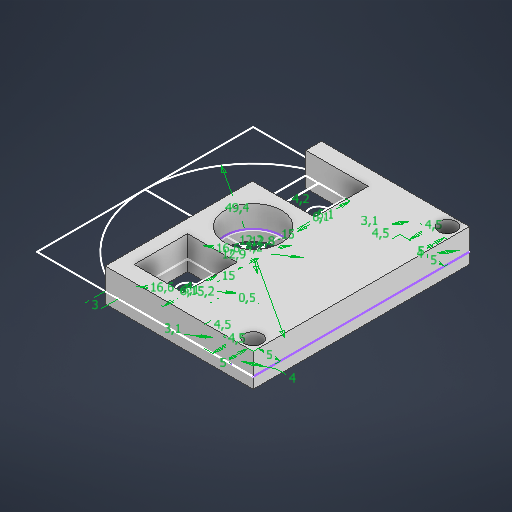
# Autodesk Inventor part: peça1
Saved by Autodesk Inventor 2026.2 (Build 302298010, 298A)
## iProperties
Created: 2026-04-17
Part Number: peça1
Material: Genérico
Document SubType Name: Modeling
Designer: a2453266
Density: 1 g/cm^3
Appearance: Padrão
Author: a2453266
## iProperties of the stored document peça1_3DPrint.ipt
Created: 2026-04-17
Part Number: peça1_3DPrint
Material: Genérico
Document SubType Name: Modeling
Designer: a2453266
Density: 1 g/cm^3
Appearance: Padrão
Author: a2453266
Autodesk Inventor part; units mm, degrees
ref_plane "YZ Plane" through (0, 0, 0) normal (1, 0, 0) x (0, 1, 0)
ref_plane "XZ Plane" through (0, 0, 0) normal (0, 1, 0) x (-1, 0, 0)
ref_plane "XY Plane" through (0, 0, 0) normal (0, 0, 1) x (1, 0, 0)
sketch "Esboço1" plane through (0, 0, 0) normal (0, 1, 0) x (-1, 0, 0)
  circle A0 centre (0, 0) radius 2.1
  line L0 (0, 0) -> (0, 15)
  circle A1 centre (0, 15) radius 2
  line L1 (0, 0) -> (0, -15)
  circle A2 centre (0, -15) radius 2.1
  line L2 (0, 15) -> (-5.2, 15)
  line L3 (-5.2, 15) -> (-5.2, -15)
  line L4 (-5.2, -15) -> (0, -15)
  circle A3 centre (0, 0) radius 6.1
  circle A4 centre (0, 0) radius 24.7
  line L5 (0, 24.7) -> (24.7, 24.7)
  line L6 (24.7, 24.7) -> (24.7, 0)
  line L7 (24.7, 0) -> (0, 0)
  line L8 (0, 0) -> (0, 24.7)
  line L9 (24.7, 0) -> (0, 0)
  line L10 (0, 0) -> (0, -24.7)
  line L11 (0, -24.7) -> (24.7, -24.7)
  line L12 (24.7, -24.7) -> (24.7, 0)
  line L13 (0, -24.7) -> (-24.7, -24.7)
  line L14 (-24.7, -24.7) -> (-24.7, 0)
  line L15 (-24.7, 0) -> (0, 0)
  line L16 (0, 0) -> (0, -24.7)
  line L17 (0, 24.7) -> (-24.7, 24.7)
  line L18 (-24.7, 24.7) -> (-24.7, 0)
  line L19 (-24.7, 0) -> (0, 0)
  line L20 (0, 0) -> (0, 24.7)
  line L21 (-5.2, 15) -> (-5.2, 24.7)
  line L22 (-5.2, -15) -> (-5.2, -24.7)
  line L23 (-5.2, 24.7) -> (-24.7, 24.7)
  line L24 (-24.7, 24.7) -> (-24.7, -24.7)
  line L25 (-24.7, -24.7) -> (-5.2, -24.7)
  line L26 (-5.2, -24.7) -> (-5.2, 24.7)
  line L27 (0, -15) -> (0, -21.1)
  line L28 (0, -21.1) -> (-5.2, -21.1)
  line L29 (0, -15) -> (0, -8.9)
  line L30 (0, -8.9) -> (-5.2, -8.9)
  line L31 (0, -8.9) -> (0, -15)
  line L32 (0, 15) -> (0, 8.9)
  line L33 (0, 15) -> (0, 21.1)
  line L34 (0, 21.1) -> (-5.2, 21.1)
  line L35 (0, 8.9) -> (-5.2, 8.9)
  line L36 (6.1, 0) -> (6.1, -24.7)
  line L37 (6.1, 0) -> (6.1, 24.7)
  line L38 (-5.2, 21.1) -> (6.1, 21.1)
  line L39 (6.1, 21.1) -> (6.1, 24.7)
  line L40 (6.1, 24.7) -> (-5.2, 24.7)
  line L41 (-5.2, 24.7) -> (-5.2, 21.1)
  line L42 (-5.2, -21.1) -> (6.1, -21.1)
  line L43 (6.1, -21.1) -> (6.1, -24.7)
  line L44 (6.1, -24.7) -> (-5.2, -24.7)
  line L45 (-5.2, -24.7) -> (-5.2, -21.1)
  line L46 (6.1, 21.1) -> (0, 21.1)
  line L47 (0, 21.1) -> (0, 8.9)
  line L48 (0, 8.9) -> (6.1, 8.9)
  line L49 (6.1, 8.9) -> (6.1, 21.1)
  line L50 (0, -8.9) -> (6.1, -8.9)
  line L51 (6.1, -8.9) -> (6.1, -21.1)
  line L52 (6.1, -21.1) -> (0, -21.1)
  line L53 (0, -21.1) -> (0, -8.9)
  line L54 (6.1, -24.7) -> (9.1, -24.7)
  line L55 (9.1, -24.7) -> (9.1, 24.7)
  line L56 (9.1, 24.7) -> (6.1, 24.7)
  line L57 (6.1, 24.7) -> (6.1, -24.7)
  circle A5 centre (0, 0) radius 8.3
  circle A6 centre (0, 15) radius 8.3
  line L58 (-5.2, -8.9) -> (-24.7, -8.9)
  line L59 (-24.7, -8.9) -> (-24.7, -24.7)
  line L60 (-24.7, -24.7) -> (-5.2, -24.7)
  line L61 (-5.2, -24.7) -> (-5.2, -8.9)
  line L62 (-5.2, 8.9) -> (-24.7, 8.9)
  line L63 (-24.7, 8.9) -> (-24.7, 24.7)
  line L64 (-24.7, 24.7) -> (-5.2, 24.7)
  line L65 (-5.2, 24.7) -> (-5.2, 8.9)
  line L66 (-8.3, 0) -> (-8.3, -8.9)
  line L67 (-8.3, 0) -> (-8.3, 8.9)
  line L68 (-8.3, -8.9) -> (-8.8, -8.9)
  line L69 (-8.8, -8.9) -> (-8.8, 8.9)
  line L70 (-8.8, 8.9) -> (-8.3, 8.9)
  line L71 (-8.3, 8.9) -> (-8.3, -8.9)
  line L72 (-8.8, -8.9) -> (-24.7, -8.9)
  line L73 (-24.7, -8.9) -> (-24.7, -24.7)
  line L74 (-24.7, -24.7) -> (-8.8, -24.7)
  line L75 (-8.8, -24.7) -> (-8.8, -8.9)
  line L76 (-8.8, -8.9) -> (-24.7, -8.9)
  line L77 (-24.7, -8.9) -> (-24.7, 24.7)
  line L78 (-24.7, 24.7) -> (-8.8, 24.7)
  line L79 (-8.8, 24.7) -> (-8.8, -8.9)
  line L80 (9.1, -24.7) -> (6.1, -24.7)
  line L81 (6.1, -24.7) -> (6.1, -21.1)
  line L82 (6.1, -21.1) -> (9.1, -21.1)
  line L83 (9.1, -21.1) -> (9.1, -24.7)
  line L84 (6.1, 21.1) -> (9.1, 21.1)
  line L85 (9.1, 21.1) -> (9.1, 24.7)
  line L86 (9.1, 24.7) -> (6.1, 24.7)
  line L87 (6.1, 24.7) -> (6.1, 21.1)
  line L88 (9.1, 24.7) -> (9.1, 22.9)
  line L89 (-24.7, -24.7) -> (-21.7, -24.7)
  line L90 (-24.7, -21.1) -> (-24.7, -24.7)
  line L91 (-24.7, 24.7) -> (-21.7, 24.7)
  line L92 (-24.7, 21.1) -> (-24.7, 24.7)
  line L93 (-24.7, -24.7) -> (-20.2, -24.7)
  line L94 (-24.7, -20.2) -> (-24.7, -24.7)
  line L95 (-24.7, 24.7) -> (-20.2, 24.7)
  line L96 (-24.7, 20.2) -> (-24.7, 24.7)
  line L97 (-8.8, -24.7) -> (-13.3, -24.7)
  line L98 (-13.3, -24.7) -> (-13.3, -20.2)
  line L99 (-13.3, -20.2) -> (-8.8, -20.2)
  line L100 (-8.8, -20.2) -> (-8.8, -24.7)
  line L101 (-8.8, 24.7) -> (-13.3, 24.7)
  line L102 (-13.3, 24.7) -> (-13.3, 20.2)
  line L103 (-13.3, 20.2) -> (-8.8, 20.2)
  line L104 (-8.8, 20.2) -> (-8.8, 24.7)
  line L105 (-13.3, -22.45) -> (-8.8, -22.45)
  line L106 (-8.8, 22.45) -> (-13.3, 22.45)
  circle A7 centre (-11.05, -22.45) radius 1.55
  circle A8 centre (-11.05, 22.45) radius 1.55
  circle A9 centre (0, 0) radius 6.4
  line L107 (9.1, 21.1) -> (6.1, 21.1)
  line L108 (6.1, 21.1) -> (6.1, 8.9)
  line L109 (6.1, 8.9) -> (9.1, 8.9)
  line L110 (9.1, 8.9) -> (9.1, 21.1)
  line L111 (6.1, -8.9) -> (9.1, -8.9)
  line L112 (9.1, -8.9) -> (9.1, -21.1)
  line L113 (9.1, -21.1) -> (6.1, -21.1)
  line L114 (6.1, -21.1) -> (6.1, -8.9)
  line L115 (-24.7, -24.7) -> (-19.7, -24.7)
  line L116 (-19.7, -24.7) -> (-19.7, -19.7)
  line L117 (-19.7, -19.7) -> (-24.7, -19.7)
  line L118 (-24.7, -19.7) -> (-24.7, -24.7)
  line L119 (-19.7, -22.2) -> (-24.7, -22.2)
  line L120 (-24.7, 24.7) -> (-19.7, 24.7)
  line L121 (-19.7, 24.7) -> (-19.7, 19.7)
  line L122 (-19.7, 19.7) -> (-24.7, 19.7)
  line L123 (-24.7, 19.7) -> (-24.7, 24.7)
  line L124 (-19.7, 22.2) -> (-24.7, 22.2)
  circle A10 centre (-22.2, -22.2) radius 2
  circle A11 centre (-22.2, 22.2) radius 2
  circle A12 centre (0, 0) radius 6.45
  point P0 (-5.2, -3.189)
  point P1 (-5.2, 3.189)
  point P2 (-5.2, 24.1464)
  point P3 (-5.2, -24.1464)
  point P4 (6.1, -21.1)
  point P5 (6.1, 21.1)
  point P6 (6.1, -21.1)
  point P7 (-5.2, 8.5308)
  point P8 (-5.6285, 8.9)
  dimension "d6" = 12.2
  dimension "d19" = 16.6
  dimension "d0" = 4.2
  dimension "d1" = 15
  dimension "d2" = 4
  dimension "d3" = 15
  dimension "d4" = 4.2
  dimension "d5" = 5.2
  dimension "d7" = 49.4
  dimension "d8" = 6.1
  dimension "d9" = 6.1
  dimension "d10" = 6.1
  dimension "d11" = 6.1
  dimension "d16" = 3
  dimension "d20" = 16.6
  dimension "d21" = 0.5
  dimension "d33" = 4.5
  dimension "d34" = 4.5
  dimension "d35" = 4.5
  dimension "d36" = 4.5
  dimension "d37" = 3.1
  dimension "d39" = 3.1
  dimension "d45" = 12.8
  dimension "d63" = 5
  dimension "d64" = 5
  dimension "d65" = 5
  dimension "d66" = 5
  dimension "d67" = 4
  dimension "d68" = 4
  dimension "d73" = 12.9
  constraints: 250 end point, 47 parallel, 33 perpendicular, 28 horizontal, 21 point on line, 13 midpoint, 11 centre point, 9 coincident, 4 point on circle, 4 vertical, 1 horizontal alignment, 5 other
  measures "d0" diameter of A0
  measures "d1" distance of L0.start L0.end
  measures "d2" diameter of A1
  measures "d3" distance of L0.start L1.end
  measures "d4" diameter of A2
  measures "d5" distance of L2.start L2.end
  measures "d7" diameter of A4
  measures "d8" distance of L4.end L27.end
  measures "d9" distance of L4.end L29.end
  measures "d10" distance of L2.start L32.end
  measures "d11" distance of L2.start L33.end
  measures "d16" distance of L56.end L55.end
  measures "d20" diameter of A6
  measures "d21" distance of L69.end L70.end
  measures "d33" distance of L98.end L99.end
  measures "d34" distance of L97.end L98.end
  measures "d35" distance of L103.end L102.end
  measures "d36" distance of L102.end L101.end
  measures "d37" diameter of A7
  measures "d39" diameter of A8
  measures "d45" diameter of A9
  measures "d63" distance of L117.end L116.end
  measures "d64" distance of L116.end L115.end
  measures "d65" distance of L121.end L122.end
  measures "d66" distance of L120.end L121.end
  measures "d67" diameter of A10
  measures "d68" diameter of A11
  measures "d73" diameter of A12
extrude "Extrusão1" add sketch "Esboço1" along normal blind 5 contours A3 L15 A9 L3 | L3 A9 L15 A3 | A9 L15 A12 L3 | L3 A12 L15 A9 | A12 L15 A5 L3 | L3 A5 L15 A12 | A5 L67 L62 A6 L3 | L3 L58 L66 A5 | L66 L58 L69 L15 | L15 L69 L62 L67 | A6 L62 L3 | L3 L22 A4 L75 L58 | L69 L58 A4 L15 | L15 A4 L62 L69 | L62 L79 A4 L21 A6 | L62 A6 L21 L3 | L75 L99 L98 A4 L58 | L62 A4 L102 L103 L79 | L75 L105 A7 A4 L98 L99 | L103 L102 A4 A8 L106 L79 | A4 A7 L105 L75 | L106 A8 A4 L79 | A4 L105 A7 | A4 L106 A8 | A7 L105 A4 | L106 A4 A8 picked at (-9.9489, -22.4881) picked at (-11.1489, 21.6171) picked at (-11.1489, -21.6171) picked at (-9.9489, 22.4881)
extrude "Extrusão2" add sketch "Esboço1" along normal blind 5 contours L36 A9 L1 A3 | A3 L0 A9 L37 | A3 L3 A9 L0 | L1 A9 L3 A3 | L36 A12 L1 A9 | A9 L0 A12 L37 | A9 L3 A12 L0 | L1 A12 L3 A9 | L36 A5 L1 A12 | A12 L0 A6 A5 L37 | A12 L3 A5 A6 L0 | L1 A5 L3 A12 | L36 L50 L1 A5 | A5 A6 L48 L37 | A6 A5 L0 | L0 A5 A6 | L1 L30 L3 A5 | A5 L0 L48 A6 | A5 A6 L3 L35 L0 | A5 L3 A6 | L36 A4 L10 L42 | L36 L11 A4 | L10 A4 L22 L28 | L37 L38 A6 L8 A4 | A4 L5 L37 | L13 L22 A4 | L38 L8 A6 | L18 L62 A4 | A4 L58 L14 | A6 L8 L34 L21 | L21 A4 L8 A6 | A4 L21 L17 | L22 L13 L75 A4 | L62 L18 L122 L121 L17 L102 A4 | A4 L98 L13 L116 L117 L14 L58 | A4 L79 L17 L21 | L75 L13 L98 L105 A7 A4 | L102 L106 A8 A4 | A4 A7 L105 L98 | L117 L116 L119 A10 L14 | L18 L124 A11 L121 L122 | A4 A8 L106 L102 L17 L79 | A7 L105 A4 | A8 L106 A4 | A4 L105 A7 | A4 L106 A8 | L13 L14 L119 A10 L116 | L124 A11 L18 L17 L121 | A10 L119 | L119 A10 | A11 L124 | L124 A11 picked at (-11.818, -22.5746) picked at (-11.7193, 22.131) picked at (-11.7193, -22.131) picked at (-11.818, 22.5746)
extrude "Extrusão3" add sketch "Esboço1" along normal blind 5 contours L37 A9 L7 | L7 A9 L36 | A9 L37 A12 L7 | L7 A12 L36 A9 | A12 L37 A5 L7 | L7 A5 L36 A12 | A5 L37 L109 L55 L7 | L7 L55 L111 L36 A5 | L111 L55 L82 L36 | L37 A6 L84 L55 L109 | L82 L55 A4 L36 | L37 A6 | L55 L84 L37 A4 | A4 L37 L5 L55 | L55 L11 L36 A4
extrude "Extrusão6" cut sketch "Esboço1" along normal through all contours L7 L0 A0 | L7 A3 L1 A0 | A0 L0 A3 L7 | A0 L1 L7 | L0 L15 A0 | A0 L15 L3 A3 L0 | L1 A3 L3 L15 A0 | A0 L15 L1 | L36 A9 L1 A3 | L37 A9 L7 | L7 A9 L36 | A3 L0 A9 L37 | A3 L3 A9 L0 | L1 A9 L3 A3 | L36 A12 L1 A9 | A9 L0 A12 L37 | L15 A3 L3 | L3 A3 L15 | A9 L3 A12 L0 | A3 L15 A9 L3 | L1 A12 L3 A9 | L3 A9 L15 A3 | A9 L15 A12 L3 | L3 A12 L15 A9
extrude "Extrusão7" cut sketch "Esboço1" along normal through all contours L7 L0 A0 | L7 A3 L1 A0 | A0 L0 A3 L7 | A0 L1 L7 | L0 L15 A0 | A0 L15 L3 A3 L0 | L1 A3 L3 L15 A0 | A0 L15 L1 | L36 A9 L1 A3 | L37 A9 L7 | L7 A9 L36 | A3 L0 A9 L37 | A3 L3 A9 L0 | L1 A9 L3 A3 | L36 A12 L1 A9 | A9 L0 A12 L37 | L15 A3 L3 | L3 A3 L15 | A9 L3 A12 L0 | A3 L15 A9 L3 | L1 A12 L3 A9 | L3 A9 L15 A3 | A9 L15 A12 L3 | L3 A12 L15 A9
extrude "Extrusão8" add sketch "Esboço1" against normal blind 2.6 contours A7 L105 A4 | A4 L105 A7 | A8 L106 A4 | A4 L106 A8 | A7 L105 A4 | A4 L105 A7 | L106 A4 A8 | A4 L106 A8
sketch "Esboço2" plane through (-9.1, 5, -24.7) normal (-1, 0, 0) x (0, 0, 1)
  point P0 (24.7, -5)
extrude "Extrusão9" cut sketch "Esboço1" along normal through all contours L111 L55 L82 L36
extrude "Extrusão10" cut sketch "Esboço1" against normal through all contours L111 L55 L82 L36
sketch "Esboço3" plane through (11.05, -2.6, -22.45) normal (0, -1, 0) x (1, 0, 0)
  circle A0 centre (0, 0) radius 1.55
  circle A1 centre (0, 44.9) radius 1.55 projected
  circle A2 centre (0, 44.9) radius 1.55
  point P0 (-11.05, 22.45)
  constraints: 2 centre point, 1 coincident
extrude "Extrusão11" cut sketch "Esboço3" against normal blind 2.6
extrude "Extrusão12" cut sketch "Esboço1" along normal blind 5 contours A10 L119 | L119 A10 | A11 L124 | L124 A11
extrude "Extrusão13" add sketch "Esboço1" against normal blind 2.5 contours L69 L58 A4 L15 | L15 A4 L62 L69 | L18 L62 A4 | A4 L58 L14 | L75 L99 L98 A4 L58 | L62 A4 L102 L103 L79 | L62 L18 L122 L121 L17 L102 A4 | A4 L98 L13 L116 L117 L14 L58 | L75 L105 A7 A4 L98 L99 | L103 L102 A4 A8 L106 L79 | L75 L13 L98 L105 A7 A4 | A4 A7 L105 L75 | L102 L106 A8 A4 | A4 A7 L105 L98 | L117 L116 L119 A10 L14 | L18 L124 A11 L121 L122 | L106 A8 A4 L79 | A4 A8 L106 L102 L17 L79 | A7 L105 A4 | A4 L105 A7 | A8 L106 A4 | A4 L106 A8 | A7 L105 A4 | A4 L105 A7 | L106 A4 A8 | A4 L106 A8 | L13 L14 L119 A10 L116 | L124 A11 L18 L17 L121
extrude "Extrusão14" add sketch "Esboço1" against normal blind 2.5 contours A9 L37 A12 L7 | L7 A12 L36 A9 | A12 L37 A5 L7 | L7 A5 L36 A12 | L36 A5 L1 A12 | A12 L0 A6 A5 L37 | A12 L3 A5 A6 L0 | L1 A5 L3 A12 | A5 L37 L109 L55 L7 | L7 L55 L111 L36 A5 | L36 L50 L1 A5 | A5 A6 L48 L37 | A6 A5 L0 | L0 A5 A6 | A12 L15 A5 L3 | L1 L30 L3 A5 | L3 A5 L15 A12 | L37 A6 L84 L55 L109 | A5 L0 L48 A6 | A5 A6 L3 L35 L0 | A5 L3 A6 | A5 L67 L62 A6 L3 | L3 L58 L66 A5 | L82 L55 A4 L36 | L36 A4 L10 L42 | L37 A6 | L66 L58 L69 L15 | L15 L69 L62 L67 | L3 L22 A4 L75 L58 | L55 L84 L37 A4 | A4 L37 L5 L55 | L55 L11 L36 A4 | L36 L11 A4 | L10 A4 L22 L28 | L62 L79 A4 L21 A6 | L62 A6 L21 L3 | L37 L38 A6 L8 A4 | A4 L5 L37 | L13 L22 A4 | L38 L8 A6 | A6 L8 L34 L21 | L21 A4 L8 A6 | A4 L21 L17 | L22 L13 L75 A4 | L103 L102 A4 A8 L106 L79 | A4 L79 L17 L21 | L102 L106 A8 A4 | L106 A8 A4 L79 | A4 A8 L106 L102 L17 L79 | A8 L106 A4 | A4 L106 A8 | L106 A4 A8 | A4 L106 A8
sketch "Esboço4" plane through (0, 5, 0) normal (0, 1, 0) x (1, 0, 0)
  circle A0 centre (0, 0) radius 6.45
  dimension "d74" = 12.9
  constraints: 1 centre point, 1 coincident
  measures "d74" diameter of A0
extrude "Extrusão15" cut sketch "Esboço4" against normal through all
